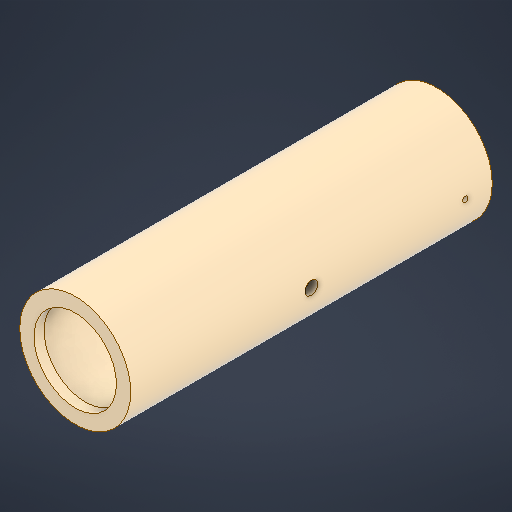
# Autodesk Inventor part: Motor tube 29mm
Saved by Autodesk Inventor 2027 (Build 310192060, 192F)
## iProperties
Created: 2026-06-24
Part Number: Motor tube 29mm
Material: Polyethylene, High Density
Document SubType Name: Modeling
Designer: troop
Density: 0.952 g/cm^3
Appearance: Smooth - Off-White
Mass: 46.6055 g
Surface Area: 227.939 cm^2
Volume: 48.9554 cm^3
Author: troop
Autodesk Inventor part; units mm, degrees
ref_plane "XZ Plane" through (0, 0, 0) normal (0, 1, 0) x (-1, 0, 0)
ref_plane "XY Plane" through (0, 0, 0) normal (0, 0, 1) x (1, 0, 0)
sketch "Sketch1" plane through (0, 0, 0) normal (0, 0, 1) x (1, 0, 0)
  circle A0 centre (0, 0) radius 14.75
  circle A1 centre (0, 0) radius 17.5
  dimension "d0" = 29.5
  dimension "d1" = 35
  constraints: 2 centre point, 2 coincident
  measures "d0" diameter of A0
  measures "d1" diameter of A1
extrude "Extrusion1" add sketch "Sketch1" along normal blind 114
ref_plane "Work Plane1" through (17.5, 0, 0) normal (1, 0, 0) x (0, 1, 0)
sketch "Sketch2" plane through (17.5, 0, 0) normal (1, 0, 0) x (0, 1, 0)
  circle A0 centre (0, 57) radius 2.05
  circle A1 centre (0, 8.477) radius 0.826
  point P0 (0, 0)
  dimension "d7" = 4.1
  dimension "d11" = 1.652
  dimension "d18" = 8.477
  dimension "d19" = 57
  dimension "d20" = 0
  dimension "d21" = 0
  constraints: 2 centre point
  measures "d7" diameter of A0
  measures "d11" diameter of A1
  measures "d18" distance of point (0, 0) A1.centre
  measures "d19" distance of A0.centre point (0, 0)
  measures "d20" horizontal distance of point (0, 0) A0.centre
  measures "d21" horizontal distance of point (0, 0) A1.centre
extrude "Extrusion2" cut sketch "Sketch2" against normal blind 114 contours A0
extrude "Extrusion3" cut sketch "Sketch2" against normal blind 10 contours A1
sketch "Sketch3" plane through (0, 0, 114) normal (0, 0, 1) x (1, 0, 0)
  circle A0 centre (0, 0) radius 13
  circle A1 centre (0, 0) radius 14.75
  dimension "d14" = 26
  dimension "d15" = 29.5
  constraints: 2 centre point, 2 coincident
  measures "d14" diameter of A0
  measures "d15" diameter of A1
extrude "Extrusion4" add sketch "Sketch3" against normal blind 3.175
body "Solid1"
